Autodesk Fusion 360 part; units mm, degrees
(part 5 of 5)
equation "d57 = plt_border_width_Ref"
equation "d58 = plt_border_width_Ref"
equation "d59 = plt_border_width_Ref"
equation "d60 = plt_border_width_Ref"
equation "d61 = plt_border_width_Ref"
equation "d62 = plt_border_width_Ref"
equation "d63 = plt_border_width_Ref"
equation "d64 = plt_border_width_Ref"
equation "d65 = plt_border_width_Ref"
equation "d66 = plt_border_width_Ref"
equation "d67 = plt_border_width_Ref"
equation "d68 = plt_border_width_Ref"
equation "d69 = plt_border_width_Ref"
equation "d70 = plt_border_width_Ref"
equation "d71 = plt_border_width_Ref"
equation "d72 = plt_border_width_Ref"
equation "d73 = plt_border_width_Ref"
equation "d74 = plt_border_width_Ref"
equation "d75 = plt_border_width_Ref"
equation "d76 = plt_border_width_Ref"
equation "d79 = ( sw_size_Ref - 18 mm ) * 0.5"
equation "d80 = ( sw_size_Ref - 18 mm ) * 0.5"
equation "d81 = sw_size_Ref * 3"
equation "d82 = sw_size_Ref * 2"
equation "d83 = plt_border_width_Ref"
equation "d84 = plt_border_width_Ref"
equation "d85 = plt_border_width_Ref"
equation "d86 = plt_border_width_Ref"
equation "d87 = plt_border_width_Ref"
equation "d88 = plt_border_width_Ref"
equation "d89 = -case_border_width_Ref"
equation "d90 = -top_inner_thickness_Ref"
equation "d92 = -case_top_thickness_Ref"
equation "case_top_thickness_Ref = 4 mm"
equation "d95 = case_border_width_Ref + plt_border_width_Ref"
equation "d96 = plt_border_width_Ref + case_border_width_Ref"
equation "d97 = sw_size_Ref"
equation "d98 = sw_size_Ref * 2"
equation "d99 = col_pinky_offset_Ref"
equation "d100 = sw_size_Ref"
equation "d101 = col_ring_offset_Ref"
equation "d102 = sw_size_Ref"
equation "d103 = col_mid_offset_Ref"
equation "d104 = sw_size_Ref"
equation "d105 = sw_size_Ref"
equation "d106 = sw_size_Ref * 5"
equation "d107 = sw_size_Ref * 2"
equation "d108 = sw_size_Ref"
equation "d109 = sw_size_Ref - col_ring_offset_Ref"
equation "d110 = sw_size_Ref - col_pinky_offset_Ref"
equation "d111 = sw_size_Ref"
equation "d112 = 4 * sw_size_Ref"
equation "d113 = 5 * sw_size_Ref"
equation "d114 = sw_size_Ref"
equation "d115 = sw_size_Ref"
equation "d116 = sw_size_Ref"
equation "d117 = sw_size_Ref * 3"
equation "d118 = sw_size_Ref"
equation "d119 = sw_size_Ref"
equation "d120 = sw_size_Ref * 2"
equation "d121 = sw_size_Ref"
equation "d122 = sw_size_Ref"
equation "d123 = sw_size_Ref"
equation "d124 = sw_size_Ref"
equation "d125 = sw_size_Ref"
equation "d128 = ( sw_size_Ref - 18 mm ) * 0.5"
equation "d129 = ( sw_size_Ref - 18 mm ) * 0.5"
equation "d130 = sw_size_Ref"
equation "d131 = sw_size_Ref"
equation "d132 = sw_size_Ref"
equation "d133 = sw_size_Ref"
equation "d134 = sw_size_Ref * 3"
equation "d135 = sw_size_Ref * 2"
equation "d136 = key_size_Ref + key_clearance_Ref"
equation "d137 = key_size_Ref + key_clearance_Ref"
equation "d140 = -sw_size_Ref"
equation "d141 = sw_size_Ref"
equation "d142 = key_size_Ref + key_clearance_Ref"
equation "d143 = key_size_Ref + key_clearance_Ref"
equation "d144 = key_size_Ref + key_clearance_Ref"
equation "d145 = key_size_Ref + key_clearance_Ref"
equation "d146 = key_size_Ref + key_clearance_Ref"
equation "d147 = key_size_Ref + key_clearance_Ref"
equation "d148 = key_size_Ref + key_clearance_Ref"
equation "d149 = key_size_Ref + key_clearance_Ref"
equation "d150 = key_size_Ref + key_clearance_Ref"
equation "d151 = key_size_Ref + key_clearance_Ref"
equation "d152 = key_size_Ref + key_clearance_Ref + sw_size_Ref"
equation "d153 = key_size_Ref + key_clearance_Ref"
equation "d154 = key_size_Ref + key_clearance_Ref + sw_size_Ref * 2"
equation "d155 = key_size_Ref + key_clearance_Ref"
equation "d156 = key_size_Ref + key_clearance_Ref"
equation "d157 = col_mid_offset_Ref"
equation "d160 = -sw_size_Ref"
equation "d164 = -sw_size_Ref"
equation "d166 = key_size_Ref + key_clearance_Ref"
equation "d167 = key_size_Ref + key_clearance_Ref"
equation "d171 = sw_size_Ref"
equation "d175 = sw_size_Ref"
equation "d179 = sw_size_Ref"
equation "d182 = -sw_size_Ref"
equation "d183 = sw_size_Ref"
equation "d187 = sw_size_Ref * 2"
equation "d191 = sw_size_Ref"
equation "d194 = key_fillet_Ref"
equation "d195 = top_align_mark_length_Ref"
equation "d196 = top_align_mark_length_Ref"
equation "d197 = top_align_mark_length_Ref"
equation "d198 = top_align_mark_length_Ref"
equation "d199 = top_align_mark_length_Ref"
equation "d200 = top_align_mark_length_Ref"
equation "d201 = top_align_mark_length_Ref"
equation "d202 = top_align_mark_length_Ref"
equation "d203 = case_border_width_Ref * 1.75"
equation "d204 = thrins_diameter_Ref"
equation "d205 = case_border_width_Ref * 1.75"
equation "d206 = case_border_width_Ref * 1.75"
equation "d207 = case_border_width_Ref * 1.75"
equation "d208 = thrins_diameter_Ref"
equation "d209 = thrins_diameter_Ref"
equation "d210 = thrins_diameter_Ref"
equation "d211 = plt_up_clearance_Ref - case_top_thickness_Ref + plt_thickness_Ref + pcb_thickness_Ref * 0.5 - thrins_depth_Ref"
equation "d213 = plt_up_clearance_Ref - case_top_thickness_Ref + plt_thickness_Ref + pcb_thickness_Ref * 0.5"
equation "top_align_mark_length_Ref = 10 mm"
equation "d216 = alignh_diameter_Ref"
equation "d217 = alignh_diameter_Ref"
equation "d218 = alignh_diameter_Ref"
equation "d219 = alignh_diameter_Ref"
equation "d224 = alignh_diameter_Ref"
equation "d226 = alignh_height_Ref"
equation "d229 = alignh_diameter_Ref * 0.5"
equation "d232 = sw_size_Ref * 0.5"
equation "d233 = sw_size_Ref * 1.5"
equation "d234 = sw_size_Ref * 1.5 + plt_border_width_Ref"
equation "d235 = sw_size_Ref * 1.5"
equation "d239 = case_top_inner_border_side_fillet_Ref"
equation "d243 = case_top_inner_border_top_fillet_Ref"
equation "pcb_clearance_Ref = 8.5 mm"
equation "case_bot_min_thickness_Ref = 3 mm"
equation "case_max_length_Ref = max(7 * sw_size_Ref + plt_border_width_Ref * 2 + case_border_width_Ref * 2; 8 * sw_size_Ref + ( plt_border_width_Ref + case_border_width_Ref ) * 2 + 7.885 mm)"
equation "case_bot_angle_Ref = 2.75 deg"
equation "case_bot_max_thickness_Ref = case_max_length_Ref / tan(90 deg - case_bot_angle_Ref) + case_bot_min_thickness_Ref"
equation "d250 = alignh_diameter_Ref"
equation "d254 = alignh_diameter_Ref"
equation "d255 = alignh_diameter_Ref"
equation "ctrl_socket_height_Ref = 4.191 mm"
equation "bat_wall_thickness_Ref = 2.5 mm"
equation "bat_offset_Ref = 25 mm + bat_wall_thickness_Ref + bat_length_Ref * 0.5"
equation "sw_hotswap_clearance_Ref = 1.9 mm"
equation "d262 = alignh_diameter_Ref"
equation "case_side_fillet_Ref = 2.5 mm"
equation "case_top_fillet_Ref = 0.5 mm"
equation "d266 = case_side_fillet_Ref"
equation "d270 = case_top_fillet_Ref"
equation "case_top_inner_border_side_fillet_Ref = 1.5 mm"
equation "case_top_inner_border_top_fillet_Ref = 1 mm"
equation "usbc_contour_height_Ref = 4.5 mm"
equation "usbc_contour_length_Ref = 12 mm"
equation "assemblyscr_head_diameter_Ref = 4.15 mm"
equation "assemblyscr_head_width_Ref = 0.85 mm"
equation "rf_diameter_Ref = 10 mm"
equation "rf_width_Ref = 0.5 mm"
equation "rf_voffset_Ref = case_border_width_Ref + 10 mm"
equation "rf_hoffset_Ref = case_border_width_Ref + 15 mm"

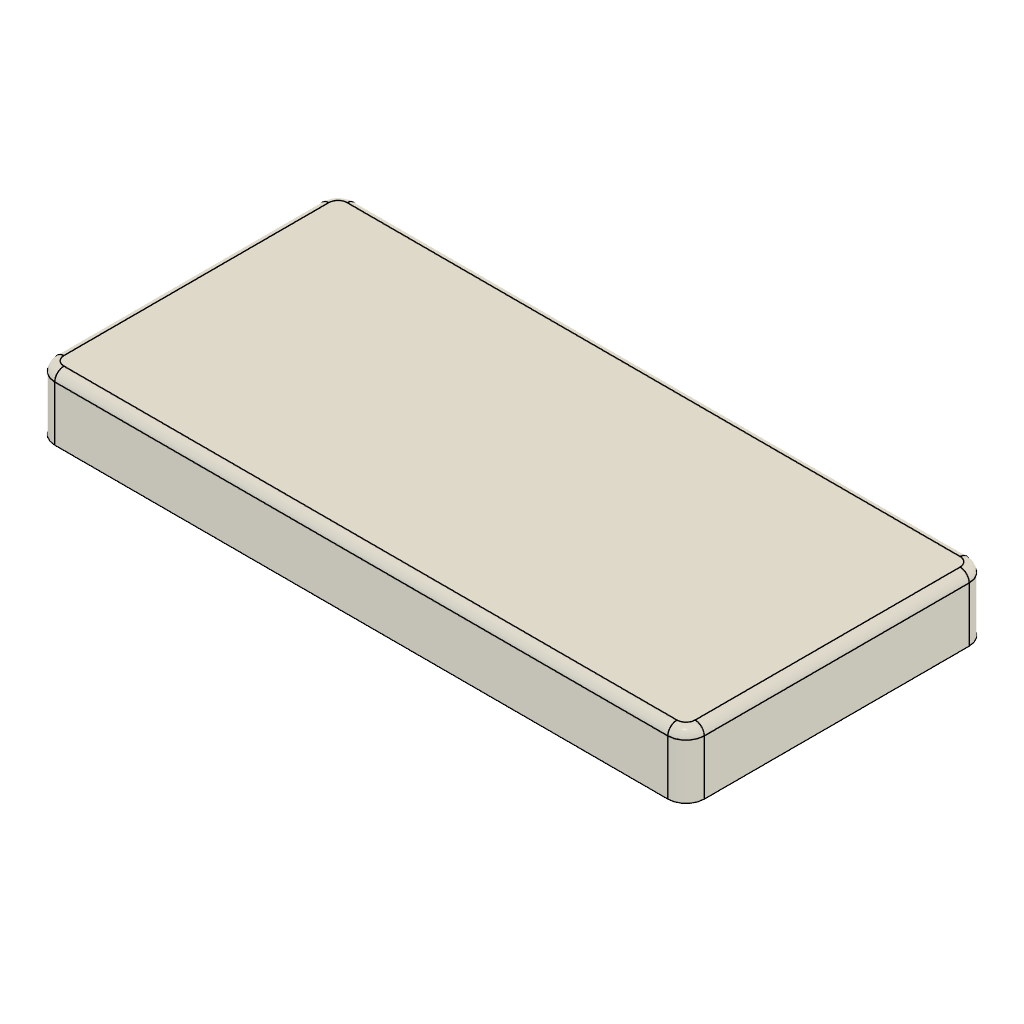
design "Keycap (2u)" references "_Globals"
part number: 2026-10-16-15-07-42-335
Autodesk Fusion 360 part; units mm, degrees
derive "Derived from _Globals"
sketch "Sketch1" plane through (0, 0, 0) normal (0, 1, 0) x (1, 0, 0)
  line L0 (17.775, 8.25) -> (-17.775, 8.25)
  line L1 (-17.775, 8.25) -> (-17.775, -8.25)
  line L2 (-17.775, -8.25) -> (17.775, -8.25)
  line L3 (17.775, -8.25) -> (17.775, 8.25)
  line L4 (17.775, 8.25) -> (-17.775, -8.25) construction
  line L5 (-17.775, 8.25) -> (17.775, -8.25) construction
  dimension "d13" = 35.55
  dimension "d14" = 16.5
  constraint horizontal L0
  constraint perpendicular L0 L1
  constraint parallel L0 L2
  constraint parallel L1 L3
  constraint coincident L4 origin
  constraint coincident L5 origin
  measures "d13" distance of L1.end L2.end
  measures "d14" distance of L0.end L1.end
extrude "Extrude1" add sketch "Sketch1" along normal blind 3.5
fillet "Fillet1" radius 0.5 4 edges at (0, 3.5, -8.25) (17.775, 3.5, 0) (0, 3.5, 8.25) (-17.775, 3.5, 0)
fillet "Fillet2" radius 1 8 edges at (17.775, 1.5, -8.25) (17.6286, 3.3536, -8.1036) (-17.6286, 3.3536, -8.1036) (-17.775, 1.5, -8.25) (-17.6286, 3.3536, 8.1036) (-17.775, 1.5, 8.25) (17.6286, 3.3536, 8.1036) (17.775, 1.5, 8.25)
shell "Shell1" thickness 1 removed faces 1 at (5.5917, 0, 2.75)
fillet "Fillet3" radius 0.5 4 edges at (-16.775, 1.25, 7.25) (16.775, 1.25, 7.25) (16.775, 1.25, -7.25) (-16.775, 1.25, -7.25)
extrude "Extrude2" add 1 faces at (-5.425, 2.5, 2.4167) along direction (0, -1, 0) blind 0.45
sketch "Sketch2" plane through (0, 2.05, 0) normal (0, -1, 0) x (1, 0, 0)
  arc A0 (-16.775, -6.75) -> (-16.275, -7.25) centre (-16.275, -6.75) ccw
  line L0 (-16.275, -7.25) -> (16.275, -7.25)
  arc A1 (16.275, -7.25) -> (16.775, -6.75) centre (16.275, -6.75) ccw
  line L1 (16.775, -6.75) -> (16.775, 6.75)
  arc A2 (16.775, 6.75) -> (16.275, 7.25) centre (16.275, 6.75) ccw
  line L2 (16.275, 7.25) -> (-16.275, 7.25)
  arc A3 (-16.275, 7.25) -> (-16.775, 6.75) centre (-16.275, 6.75) ccw
  line L3 (-16.775, 6.75) -> (-16.775, -6.75)
  line L4 (0, 0) -> (-12, 0) construction
  line L5 (-12, 0) -> (-12, 2.05) construction
  line L6 (-12.7, 2.05) -> (-11.3, 2.05)
  line L7 (-11.3, 2.05) -> (-11.3, 0.7)
  line L8 (-11.3, 0.7) -> (-9.95, 0.7)
  line L9 (-14.05, -0.7) -> (-14.05, 0.7)
  line L10 (-14.05, 0.7) -> (-12.7, 0.7)
  line L11 (-12.7, 0.7) -> (-12.7, 2.05)
  line L12 (-11.3, -2.05) -> (-12.7, -2.05)
  line L13 (-12.7, -2.05) -> (-12.7, -0.7)
  line L14 (-12.7, -0.7) -> (-14.05, -0.7)
  line L15 (-9.95, 0.7) -> (-9.95, -0.7)
  line L16 (-9.95, -0.7) -> (-11.3, -0.7)
  line L17 (-11.3, -0.7) -> (-11.3, -2.05)
  line L18 (0, 0) -> (0, 2.05) construction
  line L19 (0, 2.05) -> (-0.7, 2.05)
  line L20 (-0.7, 2.05) -> (-0.7, 0.7)
  line L21 (-0.7, 0.7) -> (-2.05, 0.7)
  line L22 (-2.05, 0.7) -> (-2.05, 0)
  line L23 (0, -2.05) -> (-0.7, -2.05)
  line L24 (-0.7, -2.05) -> (-0.7, -0.7)
  line L25 (-0.7, -0.7) -> (-2.05, -0.7)
  line L26 (-2.05, -0.7) -> (-2.05, 0)
  line L27 (12.7, 2.05) -> (11.3, 2.05)
  line L28 (11.3, 2.05) -> (11.3, 0.7)
  line L29 (11.3, 0.7) -> (9.95, 0.7)
  line L30 (9.95, 0.7) -> (9.95, -0.7)
  line L31 (11.3, -0.7) -> (11.3, -2.05)
  line L32 (9.95, -0.7) -> (11.3, -0.7)
  line L33 (11.3, -2.05) -> (12.7, -2.05)
  line L34 (12.7, -0.7) -> (14.05, -0.7)
  line L35 (12.7, -2.05) -> (12.7, -0.7)
  line L36 (14.05, -0.7) -> (14.05, 0.7)
  line L37 (12.7, 0.7) -> (12.7, 2.05)
  line L38 (14.05, 0.7) -> (12.7, 0.7)
  line L39 (0, 2.05) -> (0.7, 2.05)
  line L40 (0.7, 2.05) -> (0.7, 0.7)
  line L41 (2.05, 0.7) -> (2.05, 0)
  line L42 (0.7, 0.7) -> (2.05, 0.7)
  line L43 (0, -2.05) -> (0.7, -2.05)
  line L44 (0.7, -2.05) -> (0.7, -0.7)
  line L45 (2.05, -0.7) -> (2.05, 0)
  line L46 (0.7, -0.7) -> (2.05, -0.7)
  line L47 (-13.35, 2.7) -> (-10.65, 2.7)
  line L48 (-10.65, 2.7) -> (-10.65, 1.35)
  line L49 (-10.65, 1.35) -> (-9.3, 1.35)
  line L50 (-9.3, 1.35) -> (-9.3, -1.35)
  line L51 (-9.3, -1.35) -> (-10.65, -1.35)
  line L52 (-10.65, -1.35) -> (-10.65, -2.7)
  line L53 (-10.65, -2.7) -> (-13.35, -2.7)
  line L54 (-13.35, -2.7) -> (-13.35, -1.35)
  line L55 (-13.35, -1.35) -> (-14.7, -1.35)
  line L56 (-14.7, -1.35) -> (-14.7, 1.35)
  line L57 (-14.7, 1.35) -> (-13.35, 1.35)
  line L58 (-13.35, 1.35) -> (-13.35, 2.7)
  circle A4 centre (0, 0) radius 2.7
  line L59 (10.65, -2.7) -> (13.35, -2.7)
  line L60 (13.35, -2.7) -> (13.35, -1.35)
  line L61 (13.35, -1.35) -> (14.7, -1.35)
  line L62 (14.7, -1.35) -> (14.7, 1.35)
  line L63 (14.7, 1.35) -> (13.35, 1.35)
  line L64 (13.35, 1.35) -> (13.35, 2.7)
  line L65 (13.35, 2.7) -> (10.65, 2.7)
  line L66 (10.65, 2.7) -> (10.65, 1.35)
  line L67 (10.65, 1.35) -> (9.3, 1.35)
  line L68 (9.3, 1.35) -> (9.3, -1.35)
  line L69 (9.3, -1.35) -> (10.65, -1.35)
  line L70 (10.65, -1.35) -> (10.65, -2.7)
  dimension "d28" = 12
  dimension "d29" = 2.05
  dimension "d30" = 1.4
  dimension "d31" = 1.35
  dimension "d32" = 1.35
  dimension "d34" = 360
  dimension "d35" = 2.05
  dimension "d36" = 0.7
  dimension "d37" = 1.35
  dimension "d38" = 1.35
  dimension "d39" = -0.65
  dimension "d40" = 5.4
  dimension "d41" = 0.65
  constraint coincident L4.start L18.start
  constraint parallel L2 L4
  constraint perpendicular L4 L5
  constraint horizontal L6
  constraint midpoint L5.end L6
  constraint perpendicular L6 L7
  constraint perpendicular L7 L8
  constraint perpendicular L4 L18
  constraint perpendicular L18 L19
  constraint perpendicular L19 L20
  constraint perpendicular L20 L21
  constraint coincident L4 L22.end
  constraint perpendicular L4 L22
  constraint symmetric L4 L18.end L23.start
  constraint symmetric L4 L19.end L23.end
  constraint symmetric L4 L20.end L24.end
  constraint symmetric L4 L21.end L25.end
  constraint symmetric L4 L22.end L26.end
  constraint symmetric L6.start L18 L27.start
  constraint symmetric L6.end L18 L27.end
  constraint symmetric L7.end L18 L28.end
  constraint symmetric L8.end L18 L29.end
  constraint symmetric L9.start L18 L34.end
  constraint symmetric L9.end L18 L36.end
  constraint symmetric L10.end L18 L37.start
  constraint symmetric L12.start L18 L31.end
  constraint symmetric L12.end L18 L33.end
  constraint symmetric L13.end L18 L34.start
  constraint symmetric L15.end L18 L30.end
  constraint symmetric L16.end L18 L31.start
  constraint symmetric L19.start L18 L39.start
  constraint symmetric L18 L19.end L39.end
  constraint symmetric L18 L20.end L40.end
  constraint symmetric L18 L21.end L41.start
  constraint symmetric L18 L22.end L41.end
  constraint symmetric L18 L23.start L43.start
  constraint symmetric L18 L23.end L43.end
  constraint symmetric L18 L24.end L44.end
  constraint symmetric L18 L25.end L45.start
  measures "d28" distance of L4.start L4.end
  measures "d29" distance of L4.end L5.end
  measures "d30" distance of L6.start L6.end
  measures "d31" distance of L6.end L7.end
  measures "d32" distance of L7.end L8.end
  measures "d35" distance of L4.start L18.end
  measures "d36" distance of L18.end L19.end
  measures "d37" distance of L19.end L20.end
  measures "d38" distance of L20.end L21.end
  measures "d40" diameter of A4
extrude "Extrude3" add sketch "Sketch2" along normal blind 3.35 contours L47 L48 L49 L50 L51 L52 L53 L54 L55 L56 L57 L58 | A4 | L59 L60 L61 L62 L63 L64 L65 L66 L67 L68 L69 L70
fillet "Fillet4" radius 0.1 25 edges at (13.35, -1.3, -2.025) (14.025, -1.3, -1.35) (14.7, -1.3, 0) (14.025, -1.3, 1.35) (13.35, -1.3, 2.025) (12, -1.3, 2.7) (10.65, -1.3, 2.025) (9.975, -1.3, 1.35) (9.3, -1.3, 0) (9.975, -1.3, -1.35) (10.65, -1.3, -2.025) (12, -1.3, -2.7) (-2.5173, -1.3, -0.9764) (-9.3, -1.3, 0) (-9.975, -1.3, -1.35) (-10.65, -1.3, -2.025) (-12, -1.3, -2.7) (-13.35, -1.3, -2.025) (-14.025, -1.3, -1.35) (-14.7, -1.3, 0) (-14.025, -1.3, 1.35) (-13.35, -1.3, 2.025) (-12, -1.3, 2.7) (-10.65, -1.3, 2.025) (-9.975, -1.3, 1.35)
fillet "Fillet5" radius 0.1 24 edges at (10.65, 0.425, 2.7) (10.6793, -1.2707, 2.6707) (10.65, 0.425, 1.35) (10.6793, -1.2707, 1.3207) (9.3, 0.425, 1.35) (9.3293, -1.2707, 1.3207) (9.3, 0.425, -1.35) (9.3293, -1.2707, -1.3207) (10.65, 0.425, -1.35) (10.6793, -1.2707, -1.3207) (10.65, 0.425, -2.7) (10.6793, -1.2707, -2.6707) (13.35, 0.425, -2.7) (13.3207, -1.2707, -2.6707) (13.3207, -1.2707, -1.3207) (13.35, 0.425, -1.35) (14.6707, -1.2707, -1.3207) (14.7, 0.425, -1.35) (14.6707, -1.2707, 1.3207) (14.7, 0.425, 1.35) (13.3207, -1.2707, 1.3207) (13.35, 0.425, 1.35) (13.3207, -1.2707, 2.6707) (13.35, 0.425, 2.7)
fillet "Fillet6" radius 0.1 24 edges at (-10.6793, -1.2707, 1.3207) (-10.65, 0.425, 1.35) (-10.6793, -1.2707, 2.6707) (-10.65, 0.425, 2.7) (-13.3207, -1.2707, 2.6707) (-13.35, 0.425, 2.7) (-13.3207, -1.2707, 1.3207) (-13.35, 0.425, 1.35) (-14.6707, -1.2707, 1.3207) (-14.7, 0.425, 1.35) (-9.3293, -1.2707, 1.3207) (-9.3, 0.425, 1.35) (-10.6793, -1.2707, -1.3207) (-10.65, 0.425, -1.35) (-9.3293, -1.2707, -1.3207) (-9.3, 0.425, -1.35) (-10.6793, -1.2707, -2.6707) (-10.65, 0.425, -2.7) (-13.3207, -1.2707, -2.6707) (-13.35, 0.425, -2.7) (-13.3207, -1.2707, -1.3207) (-13.35, 0.425, -1.35) (-14.6707, -1.2707, -1.3207) (-14.7, 0.425, -1.35)
fillet "Fillet7" radius 0.1 12 edges at (-12.7, 0.375, -0.7) (-12.7, 0.375, 0.7) (-11.3, 0.375, 0.7) (-11.3, 0.375, -0.7) (0.7, 0.375, 0.7) (-0.7, 0.375, 0.7) (0.7, 0.375, -0.7) (-0.7, 0.375, -0.7) (11.3, 0.375, -0.7) (12.7, 0.375, -0.7) (12.7, 0.375, 0.7) (11.3, 0.375, 0.7)
equation "keycap_size_Ref = 16.5 mm"
equation "keycap_thickness_Ref = 3.5 mm" comment "Keycap thickness without stem"
equation "keycap_full_thickness_Ref = 4.8 mm" comment "Keycap thickness from stem to top"
equation "keycap_top_fillet_Ref = 0.5 mm"
equation "keycap_side_fillet_Ref = 1 mm"
equation "stem_fillet_Ref = 0.1 mm"
equation "stem_diameter_Ref = 5.5 mm"
equation "stem_cross_length_Ref = 4 mm"
equation "stem_cross_width_Ref = 1.3 mm"
equation "stem_offset_Ref = 0.1 mm"
equation "keycap_side_width_Ref = 1 mm"
equation "keycap_inner_thickness_Ref = keycap_full_thickness_Ref - 3.35 mm"
equation "d13 = keycap_size_Ref + switch_size_Ref"
equation "d14 = keycap_size_Ref"
equation "switch_size_Ref = 19.05 mm"
equation "d16 = keycap_thickness_Ref"
equation "d19 = keycap_top_fillet_Ref"
equation "d21 = keycap_side_fillet_Ref"
equation "d22 = keycap_side_width_Ref"
equation "d24 = keycap_side_fillet_Ref * 0.5"
equation "d25 = keycap_inner_thickness_Ref - keycap_side_width_Ref"
equation "stabilizer_distance = 12 mm"
equation "d28 = stabilizer_distance"
equation "d29 = ( stem_cross_length_Ref + stem_offset_Ref ) * 0.5"
equation "d30 = stem_cross_width_Ref + stem_offset_Ref"
equation "d31 = ( stem_cross_length_Ref - stem_cross_width_Ref ) * 0.5"
equation "d32 = ( stem_cross_length_Ref - stem_cross_width_Ref ) * 0.5"
equation "d35 = ( stem_cross_length_Ref + stem_offset_Ref ) * 0.5"
equation "d36 = ( stem_cross_width_Ref + stem_offset_Ref ) * 0.5"
equation "d37 = ( stem_cross_length_Ref - stem_cross_width_Ref ) * 0.5"
equation "d38 = ( stem_cross_length_Ref - stem_cross_width_Ref ) * 0.5"
equation "d39 = -( ( stem_diameter_Ref - stem_offset_Ref - ( stem_cross_length_Ref + stem_offset_Ref ) ) * 0.5 )"
equation "d40 = stem_diameter_Ref - stem_offset_Ref"
equation "d41 = ( ( stem_diameter_Ref - stem_offset_Ref - ( stem_cross_length_Ref + stem_offset_Ref ) ) * 0.5 )"
equation "d42 = keycap_full_thickness_Ref - keycap_inner_thickness_Ref"
equation "d45 = stem_fillet_Ref"
equation "d47 = stem_fillet_Ref"
equation "d49 = stem_fillet_Ref"
equation "d51 = stem_fillet_Ref"
named bodies: "Main"

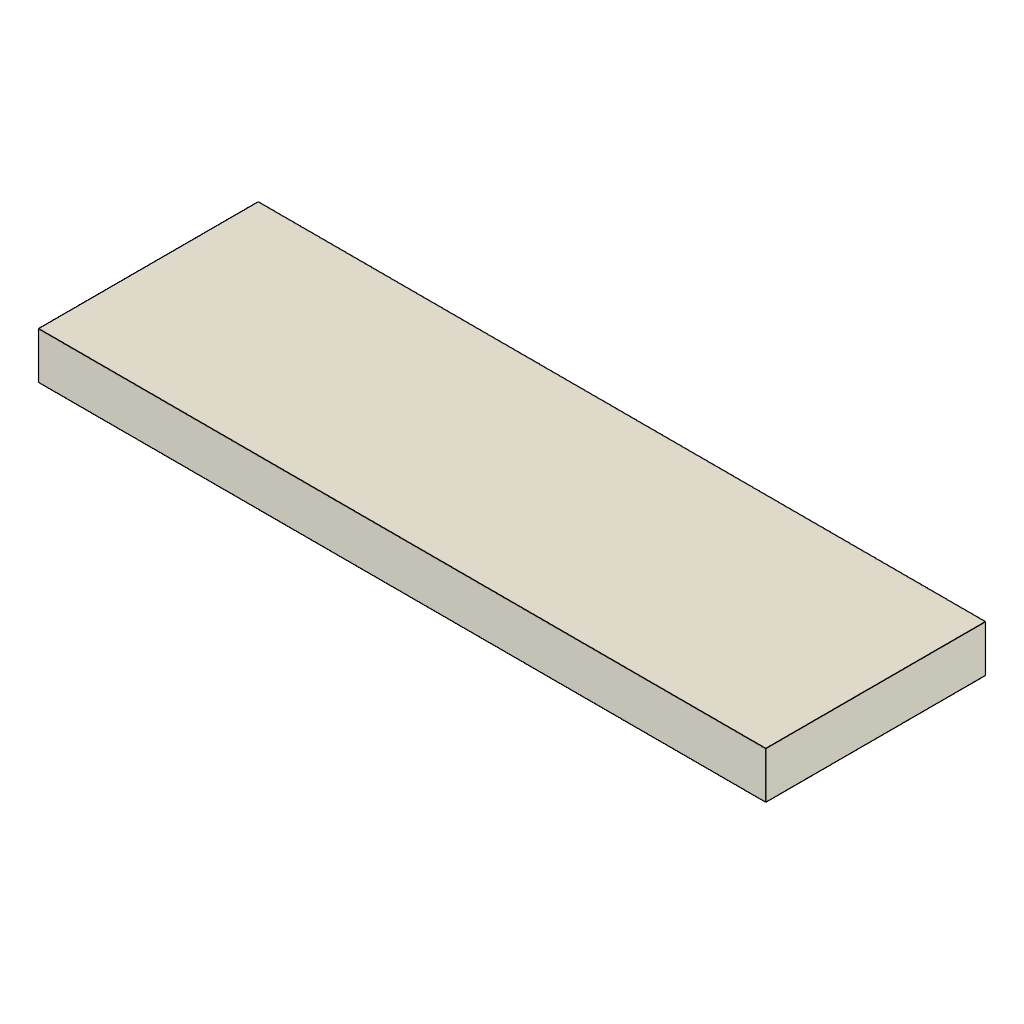
design "Keycap (3u Space base)" references "_Globals"
part number: 2026-10-16-15-32-49-082
Autodesk Fusion 360 part; units mm, degrees
derive "Derived from _Globals"
sketch "Sketch1" plane through (0, 0, 0) normal (0, 1, 0) x (1, 0, 0)
  line L0 (-27.3, -8.25) -> (27.3, -8.25)
  line L1 (27.3, -8.25) -> (27.3, 8.25)
  line L2 (27.3, 8.25) -> (-27.3, 8.25)
  line L3 (-27.3, 8.25) -> (-27.3, -8.25)
  line L4 (-27.3, -8.25) -> (27.3, 8.25) construction
  line L5 (27.3, -8.25) -> (-27.3, 8.25) construction
  dimension "d14" = 54.6
  dimension "d15" = 16.5
  constraint horizontal L0
  constraint perpendicular L0 L1
  constraint parallel L0 L2
  constraint parallel L1 L3
  constraint coincident L4 origin
  constraint coincident L5 origin
  measures "d14" distance of L1.end L2.end
  measures "d15" distance of L0.end L1.end
extrude "Extrude1" add sketch "Sketch1" along normal blind 3.5
sketch "Sketch2" plane through (0, 0, 0) normal (0, -1, 0) x (1, 0, 0)
  line L0 (-27.3, -8.25) -> (27.3, -8.25)
  line L1 (27.3, -8.25) -> (27.3, 8.25)
  line L2 (27.3, 8.25) -> (-27.3, 8.25)
  line L3 (-27.3, 8.25) -> (-27.3, -8.25)
  line L4 (26.3, 7.25) -> (-26.3, 7.25)
  line L5 (-26.3, 7.25) -> (-26.3, -7.25)
  line L6 (-26.3, -7.25) -> (26.3, -7.25)
  line L7 (26.3, -7.25) -> (26.3, 7.25)
extrude "Extrude2" cut sketch "Sketch2" against normal blind 2.05 contours L4 L5 L6 L7
sketch "Sketch3" plane through (0, 2.05, 0) normal (0, -1, 0) x (1, 0, 0)
  line L0 (26.3, -7.25) -> (26.3, 7.25)
  line L1 (26.3, 7.25) -> (-26.3, 7.25)
  line L2 (-26.3, 7.25) -> (-26.3, -7.25)
  line L3 (-26.3, -7.25) -> (26.3, -7.25)
  line L4 (0, 0) -> (-18, 0) construction
  line L5 (-18, 0) -> (-18, 2.05) construction
  line L6 (-18.7, 2.05) -> (-17.3, 2.05)
  line L7 (-17.3, 2.05) -> (-17.3, 0.7)
  line L8 (-17.3, 0.7) -> (-15.95, 0.7)
  line L9 (-20.05, -0.7) -> (-20.05, 0.7)
  line L10 (-20.05, 0.7) -> (-18.7, 0.7)
  line L11 (-18.7, 0.7) -> (-18.7, 2.05)
  line L12 (-17.3, -2.05) -> (-18.7, -2.05)
  line L13 (-18.7, -2.05) -> (-18.7, -0.7)
  line L14 (-18.7, -0.7) -> (-20.05, -0.7)
  line L15 (-15.95, 0.7) -> (-15.95, -0.7)
  line L16 (-15.95, -0.7) -> (-17.3, -0.7)
  line L17 (-17.3, -0.7) -> (-17.3, -2.05)
  line L18 (-20.7, -1.35) -> (-20.7, 1.35)
  line L19 (-20.7, 1.35) -> (-19.35, 1.35)
  line L20 (-19.35, 1.35) -> (-19.35, 2.7)
  line L21 (-19.35, 2.7) -> (-16.65, 2.7)
  line L22 (-16.65, 2.7) -> (-16.65, 1.35)
  line L23 (-16.65, 1.35) -> (-15.3, 1.35)
  line L24 (-15.3, 1.35) -> (-15.3, -1.35)
  line L25 (-15.3, -1.35) -> (-16.65, -1.35)
  line L26 (-16.65, -1.35) -> (-16.65, -2.7)
  line L27 (-16.65, -2.7) -> (-19.35, -2.7)
  line L28 (-19.35, -2.7) -> (-19.35, -1.35)
  line L29 (-19.35, -1.35) -> (-20.7, -1.35)
  line L30 (0, 0) -> (0, 2.05) construction
  line L31 (0, 2.05) -> (-0.7, 2.05)
  line L32 (-0.7, 2.05) -> (-0.7, 0.7)
  line L33 (-0.7, 0.7) -> (-2.05, 0.7)
  line L34 (-2.05, 0.7) -> (-2.05, 0)
  line L35 (0, -2.05) -> (-0.7, -2.05)
  line L36 (-0.7, -2.05) -> (-0.7, -0.7)
  line L37 (-0.7, -0.7) -> (-2.05, -0.7)
  line L38 (-2.05, -0.7) -> (-2.05, 0)
  line L39 (16.65, 1.35) -> (15.3, 1.35)
  line L40 (15.3, 1.35) -> (15.3, -1.35)
  line L41 (15.3, -1.35) -> (16.65, -1.35)
  line L42 (16.65, -1.35) -> (16.65, -2.7)
  line L43 (16.65, -2.7) -> (19.35, -2.7)
  line L44 (19.35, -2.7) -> (19.35, -1.35)
  line L45 (19.35, -1.35) -> (20.7, -1.35)
  line L46 (20.7, -1.35) -> (20.7, 1.35)
  line L47 (20.7, 1.35) -> (19.35, 1.35)
  line L48 (19.35, 1.35) -> (19.35, 2.7)
  line L49 (16.65, 2.7) -> (16.65, 1.35)
  line L50 (19.35, 2.7) -> (16.65, 2.7)
  line L51 (18.7, 2.05) -> (17.3, 2.05)
  line L52 (17.3, 0.7) -> (15.95, 0.7)
  line L53 (17.3, 2.05) -> (17.3, 0.7)
  line L54 (15.95, 0.7) -> (15.95, -0.7)
  line L55 (17.3, -0.7) -> (17.3, -2.05)
  line L56 (15.95, -0.7) -> (17.3, -0.7)
  line L57 (17.3, -2.05) -> (18.7, -2.05)
  line L58 (18.7, -0.7) -> (20.05, -0.7)
  line L59 (18.7, -2.05) -> (18.7, -0.7)
  line L60 (20.05, -0.7) -> (20.05, 0.7)
  line L61 (20.05, 0.7) -> (18.7, 0.7)
  line L62 (18.7, 0.7) -> (18.7, 2.05)
  line L63 (0, 2.05) -> (0.7, 2.05)
  line L64 (0.7, 0.7) -> (2.05, 0.7)
  line L65 (2.05, 0.7) -> (2.05, 0)
  line L66 (0.7, 2.05) -> (0.7, 0.7)
  line L67 (0, -2.05) -> (0.7, -2.05)
  line L68 (0.7, -2.05) -> (0.7, -0.7)
  line L69 (2.05, -0.7) -> (2.05, 0)
  line L70 (0.7, -0.7) -> (2.05, -0.7)
  circle A0 centre (0, 0) radius 2.7
  dimension "d26" = 18
  dimension "d27" = 2.05
  dimension "d28" = 1.4
  dimension "d29" = 1.35
  dimension "d30" = 1.35
  dimension "d32" = 360
  dimension "d33" = -0.65
  dimension "d34" = 2.05
  dimension "d35" = 0.7
  dimension "d36" = 1.35
  dimension "d37" = 1.35
  dimension "d38" = 5.4
  constraint coincident L4.start L30.start
  constraint horizontal L4
  constraint perpendicular L4 L5
  constraint horizontal L6
  constraint midpoint L5.end L6
  constraint perpendicular L6 L7
  constraint perpendicular L7 L8
  constraint perpendicular L4 L30
  constraint perpendicular L30 L31
  constraint perpendicular L31 L32
  constraint perpendicular L32 L33
  constraint coincident L4 L34.end
  constraint perpendicular L4 L34
  constraint symmetric L4 L30.end L35.start
  constraint symmetric L4 L31.end L35.end
  constraint symmetric L4 L32.end L36.end
  constraint symmetric L4 L33.end L37.end
  constraint symmetric L4 L34.end L38.end
  constraint symmetric L6.start L30 L51.start
  constraint symmetric L6.end L30 L51.end
  constraint symmetric L7.end L30 L52.start
  constraint symmetric L8.end L30 L52.end
  constraint symmetric L9.start L30 L58.end
  constraint symmetric L9.end L30 L60.end
  constraint symmetric L10.end L30 L61.end
  constraint symmetric L12.start L30 L55.end
  constraint symmetric L12.end L30 L57.end
  constraint symmetric L13.end L30 L58.start
  constraint symmetric L15.end L30 L54.end
  constraint symmetric L16.end L30 L55.start
  constraint symmetric L18.start L30 L45.end
  constraint symmetric L18.end L30 L46.end
  constraint symmetric L19.end L30 L47.end
  constraint symmetric L20.end L30 L48.end
  constraint symmetric L21.end L30 L49.start
  constraint symmetric L22.end L30 L39.start
  constraint symmetric L23.end L30 L39.end
  constraint symmetric L24.end L30 L40.end
  constraint symmetric L25.end L30 L41.end
  constraint symmetric L26.end L30 L42.end
  constraint symmetric L27.end L30 L43.end
  constraint symmetric L28.end L30 L44.end
  constraint symmetric L31.start L30 L63.start
  constraint symmetric L30 L31.end L63.end
  constraint symmetric L30 L32.end L64.start
  constraint symmetric L30 L33.end L64.end
  constraint symmetric L30 L34.end L65.end
  constraint symmetric L30 L35.start L67.start
  constraint symmetric L30 L35.end L67.end
  constraint symmetric L30 L36.end L68.end
  constraint symmetric L30 L37.end L69.start
  measures "d26" distance of L4.start L4.end
  measures "d27" distance of L4.end L5.end
  measures "d28" distance of L6.start L6.end
  measures "d29" distance of L6.end L7.end
  measures "d30" distance of L7.end L8.end
  measures "d34" distance of L4.start L30.end
  measures "d35" distance of L30.end L31.end
  measures "d36" distance of L31.end L32.end
  measures "d37" distance of L32.end L33.end
  measures "d38" diameter of A0
extrude "Extrude3" add sketch "Sketch3" along normal blind 3.35 contours L18 L19 L20 L21 L22 L23 L24 L25 L26 L27 L28 L29 | L39 L40 L41 L42 L43 L44 L45 L46 L47 L48 L49 L50 | A0
fillet "Fillet3" radius 0.1 5 edges at (-2.5173, -1.3, -0.9764) (0.7, 0.375, -0.7) (-0.7, 0.375, -0.7) (0.7, 0.375, 0.7) (-0.7, 0.375, 0.7)
fillet "Fillet4" radius 0.1 28 edges at (19.35, 0.375, -2.7) (19.35, 0.375, -1.35) (20.7, 0.375, -1.35) (20.7, 0.375, 1.35) (19.35, 0.375, 1.35) (19.35, 0.375, 2.7) (16.65, 0.375, 2.7) (16.65, 0.375, 1.35) (15.3, 0.375, 1.35) (15.3, 0.375, -1.35) (16.65, 0.375, -1.35) (16.65, 0.375, -2.7) (16.65, -1.3, -2.025) (18, -1.3, -2.7) (15.975, -1.3, -1.35) (15.3, -1.3, 0) (15.975, -1.3, 1.35) (16.65, -1.3, 2.025) (18, -1.3, 2.7) (19.35, -1.3, 2.025) (20.025, -1.3, 1.35) (20.7, -1.3, 0) (20.025, -1.3, -1.35) (19.35, -1.3, -2.025) (18.7, 0.375, -0.7) (18.7, 0.375, 0.7) (17.3, 0.375, 0.7) (17.3, 0.375, -0.7)
fillet "Fillet5" radius 0.1 28 edges at (-16.65, 0.375, 2.7) (-19.35, 0.375, 2.7) (-20.7, 0.375, 1.35) (-15.3, 0.375, 1.35) (-15.975, -1.3, 1.35) (-16.65, -1.3, 2.025) (-18, -1.3, 2.7) (-19.35, -1.3, 2.025) (-20.025, -1.3, 1.35) (-16.65, 0.375, 1.35) (-19.35, 0.375, 1.35) (-20.7, -1.3, 0) (-20.7, 0.375, -1.35) (-19.35, 0.375, -1.35) (-20.025, -1.3, -1.35) (-19.35, -1.3, -2.025) (-19.35, 0.375, -2.7) (-18, -1.3, -2.7) (-16.65, 0.375, -2.7) (-16.65, -1.3, -2.025) (-16.65, 0.375, -1.35) (-15.975, -1.3, -1.35) (-15.3, 0.375, -1.35) (-15.3, -1.3, 0) (-17.3, 0.375, -0.7) (-18.7, 0.375, -0.7) (-17.3, 0.375, 0.7) (-18.7, 0.375, 0.7)
fillet "Fillet6" radius 0.5 4 edges at (26.3, 1.025, -7.25) (26.3, 1.025, 7.25) (-26.3, 1.025, 7.25) (-26.3, 1.025, -7.25)
equation "keycap_size_Ref = 16.5 mm"
equation "keycap_thickness_Ref = 3.5 mm" comment "Keycap thickness without stem"
equation "keycap_full_thickness_Ref = 4.8 mm" comment "Keycap thickness from stem to top"
equation "keycap_top_fillet_Ref = 0.5 mm"
equation "keycap_side_fillet_Ref = 1 mm"
equation "stem_fillet_Ref = 0.1 mm"
equation "stem_diameter_Ref = 5.5 mm"
equation "stem_cross_length_Ref = 4 mm"
equation "stem_cross_width_Ref = 1.3 mm"
equation "stem_offset_Ref = 0.1 mm"
equation "keycap_side_width_Ref = 1 mm"
equation "keycap_inner_thickness_Ref = keycap_full_thickness_Ref - 3.35 mm"
equation "switch_size_Ref = 19.05 mm"
equation "d14 = keycap_size_Ref + switch_size_Ref * 2"
equation "d15 = keycap_size_Ref"
equation "d16 = keycap_thickness_Ref"
equation "d22 = -keycap_side_width_Ref"
equation "d23 = -( keycap_thickness_Ref - keycap_inner_thickness_Ref )"
equation "stabilizer_distance = 18 mm"
equation "d26 = stabilizer_distance"
equation "d27 = ( stem_cross_length_Ref + stem_offset_Ref ) * 0.5"
equation "d28 = stem_cross_width_Ref + stem_offset_Ref"
equation "d29 = ( stem_cross_length_Ref - stem_cross_width_Ref ) * 0.5"
equation "d30 = ( stem_cross_length_Ref - stem_cross_width_Ref ) * 0.5"
equation "d33 = -( ( stem_diameter_Ref - stem_offset_Ref - ( stem_cross_length_Ref + stem_offset_Ref ) ) * 0.5 )"
equation "d34 = ( stem_cross_length_Ref + stem_offset_Ref ) * 0.5"
equation "d35 = ( stem_cross_width_Ref + stem_offset_Ref ) * 0.5"
equation "d36 = ( stem_cross_length_Ref - stem_cross_width_Ref ) * 0.5"
equation "d37 = ( stem_cross_length_Ref - stem_cross_width_Ref ) * 0.5"
equation "d38 = stem_diameter_Ref - stem_offset_Ref"
equation "d39 = keycap_full_thickness_Ref - keycap_inner_thickness_Ref"
equation "d42 = stem_fillet_Ref"
equation "d44 = stem_fillet_Ref"
equation "d46 = stem_fillet_Ref"
equation "d48 = keycap_side_fillet_Ref * 0.5"
named bodies: "Main"
